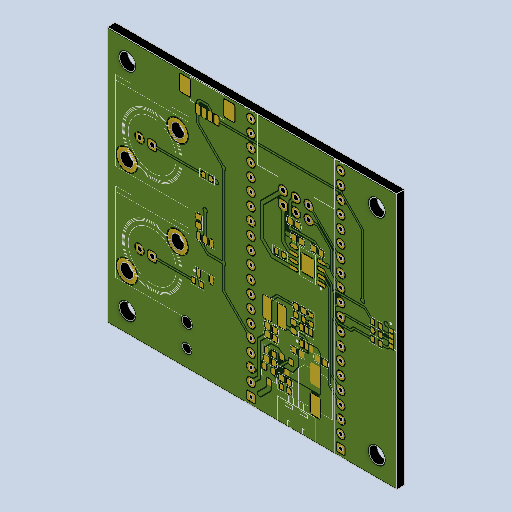
# Autodesk Inventor part: AEON_Feeder_ApplicationBoard_BOARD
Saved by Autodesk Inventor 2025.4 (Build 294407000, 407)
## iProperties
Created: 2026-07-15
Part Number: AEON_Feeder_ApplicationBoard_BOARD
Material: Generic
Document SubType Name: Modeling
Designer: Yuhsuan Chen
Density: 1 g/cm^3
Appearance: BoardColor
Author: Yuhsuan Chen
Autodesk Inventor part; units mm, degrees
ref_plane "YZ Plane" through (0, 0, 0) normal (1, 0, 0) x (0, 1, 0)
ref_plane "XZ Plane" through (0, 0, 0) normal (0, 1, 0) x (-1, 0, 0)
ref_plane "BoardFrontPlane" through (0, 0, 0) normal (0, 0, 1) x (1, 0, 0)
sketch "Sketch1" plane through (0, 0, 0) normal (0, 0, 1) x (1, 0, 0)
  line L0 (60.5, 48.83) -> (60.5, 100.155)
  line L1 (60.5, 100.155) -> (118.5, 100.155)
  line L2 (118.5, 100.155) -> (118.5, 48.83)
  line L3 (118.5, 48.83) -> (60.5, 48.83)
  constraints: 8 end point
extrude "BoardOutline" add sketch "Sketch1" along normal blind 1.5954
sketch "img_Top" plane through (0, 0, 1.5954) normal (0, 0, 1) x (1, 0, 0)
  line L0 (60.5, 100.155) -> (118.5, 100.155) construction
  line L1 (118.5, 100.155) -> (118.5, 48.8112) construction
  line L2 (118.5, 48.8112) -> (60.5, 48.8112) construction
  line L3 (60.5, 48.8112) -> (60.5, 100.155) construction
  constraints: 2 other
decal "Decal_Top"
sketch "img_Bottom" plane through (0, 0, -1.5954) normal (0, 0, -1) x (1, 0, 0)
  line L0 (60.5, -48.83) -> (118.5, -48.83) construction
  line L1 (118.5, -48.83) -> (118.5, -100.1738) construction
  line L2 (118.5, -100.1738) -> (60.5, -100.1738) construction
  line L3 (60.5, -100.1738) -> (60.5, -48.83) construction
  constraints: 2 other
decal "Decal_Bottom"
sketch "Sketch4" plane through (0, 0, 1.5954) normal (0, 0, 1) x (1, 0, 0)
  point P0 (76.45, 52.33)
hole "J7-0_RWRNLWJQ" at (76.45, 52.33, 1.5954) direction (0, 0, -1) diameter 1.7 end through all
sketch "Sketch5" plane through (0, 0, 1.5954) normal (0, 0, 1) x (1, 0, 0)
  point P0 (76.45, 56.83)
hole "J7-0_PDRFSNQX" at (76.45, 56.83, 1.5954) direction (0, 0, -1) diameter 1.9 end through all
sketch "Sketch6" plane through (0, 0, 1.5954) normal (0, 0, 1) x (1, 0, 0)
  point P0 (69.5, 84.155)
hole "J4-1" at (69.5, 84.155, 1.5954) direction (0, 0, -1) diameter 1 end through all
sketch "Sketch7" plane through (0, 0, 1.5954) normal (0, 0, 1) x (1, 0, 0)
  point P0 (74.58, 89.235)
hole "J4-2_QVPFGWQR" at (74.58, 89.235, 1.5954) direction (0, 0, -1) diameter 2.64 end through all
sketch "Sketch8" plane through (0, 0, 1.5954) normal (0, 0, 1) x (1, 0, 0)
  point P0 (64.42, 79.075)
hole "J4-2_MQRSTWXM" at (64.42, 79.075, 1.5954) direction (0, 0, -1) diameter 2.64 end through all
sketch "Sketch9" plane through (0, 0, 1.5954) normal (0, 0, 1) x (1, 0, 0)
  point P0 (66.96, 84.155)
hole "J4-2_IIDURWUS" at (66.96, 84.155, 1.5954) direction (0, 0, -1) diameter 1 end through all
sketch "Sketch10" plane through (0, 0, 1.5954) normal (0, 0, 1) x (1, 0, 0)
  point P0 (69.5, 64.83)
hole "J5-1" at (69.5, 64.83, 1.5954) direction (0, 0, -1) diameter 1 end through all
sketch "Sketch11" plane through (0, 0, 1.5954) normal (0, 0, 1) x (1, 0, 0)
  point P0 (74.58, 69.91)
hole "J5-2_LCPFIACD" at (74.58, 69.91, 1.5954) direction (0, 0, -1) diameter 2.64 end through all
sketch "Sketch12" plane through (0, 0, 1.5954) normal (0, 0, 1) x (1, 0, 0)
  point P0 (64.42, 59.75)
hole "J5-2_QQKSJXMX" at (64.42, 59.75, 1.5954) direction (0, 0, -1) diameter 2.64 end through all
sketch "Sketch13" plane through (0, 0, 1.5954) normal (0, 0, 1) x (1, 0, 0)
  point P0 (66.96, 64.83)
hole "J5-2_OMAKYWNI" at (66.96, 64.83, 1.5954) direction (0, 0, -1) diameter 1 end through all
sketch "Sketch14" plane through (0, 0, 1.5954) normal (0, 0, 1) x (1, 0, 0)
  point P0 (100.815, 89.37)
hole "J1-6" at (100.815, 89.37, 1.5954) direction (0, 0, -1) diameter 1.02 end through all
sketch "Sketch15" plane through (0, 0, 1.5954) normal (0, 0, 1) x (1, 0, 0)
  point P0 (100.815, 86.83)
hole "J1-5" at (100.815, 86.83, 1.5954) direction (0, 0, -1) diameter 1.02 end through all
sketch "Sketch16" plane through (0, 0, 1.5954) normal (0, 0, 1) x (1, 0, 0)
  point P0 (98.275, 89.37)
hole "J1-4" at (98.275, 89.37, 1.5954) direction (0, 0, -1) diameter 1.02 end through all
sketch "Sketch17" plane through (0, 0, 1.5954) normal (0, 0, 1) x (1, 0, 0)
  point P0 (98.275, 86.83)
hole "J1-3" at (98.275, 86.83, 1.5954) direction (0, 0, -1) diameter 1.02 end through all
sketch "Sketch18" plane through (0, 0, 1.5954) normal (0, 0, 1) x (1, 0, 0)
  point P0 (95.735, 89.37)
hole "J1-2" at (95.735, 89.37, 1.5954) direction (0, 0, -1) diameter 1.02 end through all
sketch "Sketch19" plane through (0, 0, 1.5954) normal (0, 0, 1) x (1, 0, 0)
  point P0 (95.735, 86.83)
hole "J1-1" at (95.735, 86.83, 1.5954) direction (0, 0, -1) diameter 1.02 end through all
sketch "Sketch20" plane through (0, 0, 1.5954) normal (0, 0, 1) x (1, 0, 0)
  point P0 (89.275, 98.605)
hole "J3-20" at (89.275, 98.605, 1.5954) direction (0, 0, -1) diameter 0.8 end through all
sketch "Sketch21" plane through (0, 0, 1.5954) normal (0, 0, 1) x (1, 0, 0)
  point P0 (89.275, 83.365)
hole "J3-14" at (89.275, 83.365, 1.5954) direction (0, 0, -1) diameter 0.8 end through all
sketch "Sketch22" plane through (0, 0, 1.5954) normal (0, 0, 1) x (1, 0, 0)
  point P0 (89.275, 78.285)
hole "J3-12" at (89.275, 78.285, 1.5954) direction (0, 0, -1) diameter 0.8 end through all
sketch "Sketch23" plane through (0, 0, 1.5954) normal (0, 0, 1) x (1, 0, 0)
  point P0 (89.275, 96.065)
hole "J3-19" at (89.275, 96.065, 1.5954) direction (0, 0, -1) diameter 0.8 end through all
sketch "Sketch24" plane through (0, 0, 1.5954) normal (0, 0, 1) x (1, 0, 0)
  point P0 (89.275, 85.905)
hole "J3-15" at (89.275, 85.905, 1.5954) direction (0, 0, -1) diameter 0.8 end through all
sketch "Sketch25" plane through (0, 0, 1.5954) normal (0, 0, 1) x (1, 0, 0)
  point P0 (89.275, 75.745)
hole "J3-11" at (89.275, 75.745, 1.5954) direction (0, 0, -1) diameter 0.8 end through all
sketch "Sketch26" plane through (0, 0, 1.5954) normal (0, 0, 1) x (1, 0, 0)
  point P0 (89.275, 88.445)
hole "J3-16" at (89.275, 88.445, 1.5954) direction (0, 0, -1) diameter 0.8 end through all
sketch "Sketch27" plane through (0, 0, 1.5954) normal (0, 0, 1) x (1, 0, 0)
  point P0 (89.275, 90.985)
hole "J3-17" at (89.275, 90.985, 1.5954) direction (0, 0, -1) diameter 0.8 end through all
sketch "Sketch28" plane through (0, 0, 1.5954) normal (0, 0, 1) x (1, 0, 0)
  point P0 (89.275, 68.125)
hole "J3-8" at (89.275, 68.125, 1.5954) direction (0, 0, -1) diameter 0.8 end through all
sketch "Sketch29" plane through (0, 0, 1.5954) normal (0, 0, 1) x (1, 0, 0)
  point P0 (89.275, 65.585)
hole "J3-7" at (89.275, 65.585, 1.5954) direction (0, 0, -1) diameter 0.8 end through all
sketch "Sketch30" plane through (0, 0, 1.5954) normal (0, 0, 1) x (1, 0, 0)
  point P0 (89.275, 63.045)
hole "J3-6" at (89.275, 63.045, 1.5954) direction (0, 0, -1) diameter 0.8 end through all
sketch "Sketch31" plane through (0, 0, 1.5954) normal (0, 0, 1) x (1, 0, 0)
  point P0 (89.275, 50.345)
hole "J3-1" at (89.275, 50.345, 1.5954) direction (0, 0, -1) diameter 0.8 end through all
sketch "Sketch32" plane through (0, 0, 1.5954) normal (0, 0, 1) x (1, 0, 0)
  point P0 (89.275, 70.665)
hole "J3-9" at (89.275, 70.665, 1.5954) direction (0, 0, -1) diameter 0.8 end through all
sketch "Sketch33" plane through (0, 0, 1.5954) normal (0, 0, 1) x (1, 0, 0)
  point P0 (89.275, 52.885)
hole "J3-2" at (89.275, 52.885, 1.5954) direction (0, 0, -1) diameter 0.8 end through all
sketch "Sketch34" plane through (0, 0, 1.5954) normal (0, 0, 1) x (1, 0, 0)
  point P0 (89.275, 57.965)
hole "J3-4" at (89.275, 57.965, 1.5954) direction (0, 0, -1) diameter 0.8 end through all
sketch "Sketch35" plane through (0, 0, 1.5954) normal (0, 0, 1) x (1, 0, 0)
  point P0 (89.275, 73.205)
hole "J3-10" at (89.275, 73.205, 1.5954) direction (0, 0, -1) diameter 0.8 end through all
sketch "Sketch36" plane through (0, 0, 1.5954) normal (0, 0, 1) x (1, 0, 0)
  point P0 (89.275, 60.505)
hole "J3-5" at (89.275, 60.505, 1.5954) direction (0, 0, -1) diameter 0.8 end through all
sketch "Sketch37" plane through (0, 0, 1.5954) normal (0, 0, 1) x (1, 0, 0)
  point P0 (89.275, 55.425)
hole "J3-3" at (89.275, 55.425, 1.5954) direction (0, 0, -1) diameter 0.8 end through all
sketch "Sketch38" plane through (0, 0, 1.5954) normal (0, 0, 1) x (1, 0, 0)
  point P0 (89.275, 80.825)
hole "J3-13" at (89.275, 80.825, 1.5954) direction (0, 0, -1) diameter 0.8 end through all
sketch "Sketch39" plane through (0, 0, 1.5954) normal (0, 0, 1) x (1, 0, 0)
  point P0 (89.275, 93.525)
hole "J3-18" at (89.275, 93.525, 1.5954) direction (0, 0, -1) diameter 0.8 end through all
sketch "Sketch40" plane through (0, 0, 1.5954) normal (0, 0, 1) x (1, 0, 0)
  point P0 (107.275, 98.605)
hole "J2-20" at (107.275, 98.605, 1.5954) direction (0, 0, -1) diameter 0.8 end through all
sketch "Sketch41" plane through (0, 0, 1.5954) normal (0, 0, 1) x (1, 0, 0)
  point P0 (107.275, 96.065)
hole "J2-19" at (107.275, 96.065, 1.5954) direction (0, 0, -1) diameter 0.8 end through all
sketch "Sketch42" plane through (0, 0, 1.5954) normal (0, 0, 1) x (1, 0, 0)
  point P0 (107.275, 85.905)
hole "J2-15" at (107.275, 85.905, 1.5954) direction (0, 0, -1) diameter 0.8 end through all
sketch "Sketch43" plane through (0, 0, 1.5954) normal (0, 0, 1) x (1, 0, 0)
  point P0 (107.275, 75.745)
hole "J2-11" at (107.275, 75.745, 1.5954) direction (0, 0, -1) diameter 0.8 end through all
sketch "Sketch44" plane through (0, 0, 1.5954) normal (0, 0, 1) x (1, 0, 0)
  point P0 (107.275, 88.445)
hole "J2-16" at (107.275, 88.445, 1.5954) direction (0, 0, -1) diameter 0.8 end through all
sketch "Sketch45" plane through (0, 0, 1.5954) normal (0, 0, 1) x (1, 0, 0)
  point P0 (107.275, 90.985)
hole "J2-17" at (107.275, 90.985, 1.5954) direction (0, 0, -1) diameter 0.8 end through all
sketch "Sketch46" plane through (0, 0, 1.5954) normal (0, 0, 1) x (1, 0, 0)
  point P0 (107.275, 65.585)
hole "J2-7" at (107.275, 65.585, 1.5954) direction (0, 0, -1) diameter 0.8 end through all
sketch "Sketch47" plane through (0, 0, 1.5954) normal (0, 0, 1) x (1, 0, 0)
  point P0 (107.275, 63.045)
hole "J2-6" at (107.275, 63.045, 1.5954) direction (0, 0, -1) diameter 0.8 end through all
sketch "Sketch48" plane through (0, 0, 1.5954) normal (0, 0, 1) x (1, 0, 0)
  point P0 (107.275, 50.345)
hole "J2-1" at (107.275, 50.345, 1.5954) direction (0, 0, -1) diameter 0.8 end through all
sketch "Sketch49" plane through (0, 0, 1.5954) normal (0, 0, 1) x (1, 0, 0)
  point P0 (107.275, 60.505)
hole "J2-5" at (107.275, 60.505, 1.5954) direction (0, 0, -1) diameter 0.8 end through all
sketch "Sketch50" plane through (0, 0, 1.5954) normal (0, 0, 1) x (1, 0, 0)
  point P0 (107.275, 70.665)
hole "J2-9" at (107.275, 70.665, 1.5954) direction (0, 0, -1) diameter 0.8 end through all
sketch "Sketch51" plane through (0, 0, 1.5954) normal (0, 0, 1) x (1, 0, 0)
  point P0 (107.275, 52.885)
hole "J2-2" at (107.275, 52.885, 1.5954) direction (0, 0, -1) diameter 0.8 end through all
sketch "Sketch52" plane through (0, 0, 1.5954) normal (0, 0, 1) x (1, 0, 0)
  point P0 (107.275, 57.965)
hole "J2-4" at (107.275, 57.965, 1.5954) direction (0, 0, -1) diameter 0.8 end through all
sketch "Sketch53" plane through (0, 0, 1.5954) normal (0, 0, 1) x (1, 0, 0)
  point P0 (107.275, 73.205)
hole "J2-10" at (107.275, 73.205, 1.5954) direction (0, 0, -1) diameter 0.8 end through all
sketch "Sketch54" plane through (0, 0, 1.5954) normal (0, 0, 1) x (1, 0, 0)
  point P0 (107.275, 83.365)
hole "J2-14" at (107.275, 83.365, 1.5954) direction (0, 0, -1) diameter 0.8 end through all
sketch "Sketch55" plane through (0, 0, 1.5954) normal (0, 0, 1) x (1, 0, 0)
  point P0 (107.275, 78.285)
hole "J2-12" at (107.275, 78.285, 1.5954) direction (0, 0, -1) diameter 0.8 end through all
sketch "Sketch56" plane through (0, 0, 1.5954) normal (0, 0, 1) x (1, 0, 0)
  point P0 (107.275, 93.525)
hole "J2-18" at (107.275, 93.525, 1.5954) direction (0, 0, -1) diameter 0.8 end through all
sketch "Sketch57" plane through (0, 0, 1.5954) normal (0, 0, 1) x (1, 0, 0)
  point P0 (107.275, 80.825)
hole "J2-13" at (107.275, 80.825, 1.5954) direction (0, 0, -1) diameter 0.8 end through all
sketch "Sketch58" plane through (0, 0, 1.5954) normal (0, 0, 1) x (1, 0, 0)
  point P0 (107.275, 68.125)
hole "J2-8" at (107.275, 68.125, 1.5954) direction (0, 0, -1) diameter 0.8 end through all
sketch "Sketch59" plane through (0, 0, 1.5954) normal (0, 0, 1) x (1, 0, 0)
  point P0 (107.275, 55.425)
hole "J2-3" at (107.275, 55.425, 1.5954) direction (0, 0, -1) diameter 0.8 end through all
sketch "Sketch60" plane through (0, 0, 1.5954) normal (0, 0, 1) x (1, 0, 0)
  point P0 (114.5, 52.83)
hole "Free-MH4" at (114.5, 52.83, 1.5954) direction (0, 0, -1) diameter 3.1 end through all
sketch "Sketch61" plane through (0, 0, 1.5954) normal (0, 0, 1) x (1, 0, 0)
  point P0 (114.5, 95.83)
hole "Free-MH3" at (114.5, 95.83, 1.5954) direction (0, 0, -1) diameter 3.1 end through all
sketch "Sketch62" plane through (0, 0, 1.5954) normal (0, 0, 1) x (1, 0, 0)
  point P0 (64.5, 96.155)
hole "Free-MH2" at (64.5, 96.155, 1.5954) direction (0, 0, -1) diameter 3.1 end through all
sketch "Sketch63" plane through (0, 0, 1.5954) normal (0, 0, 1) x (1, 0, 0)
  point P0 (64.5, 52.83)
hole "Free-MH1" at (64.5, 52.83, 1.5954) direction (0, 0, -1) diameter 3.1 end through all
body "Solid1"
